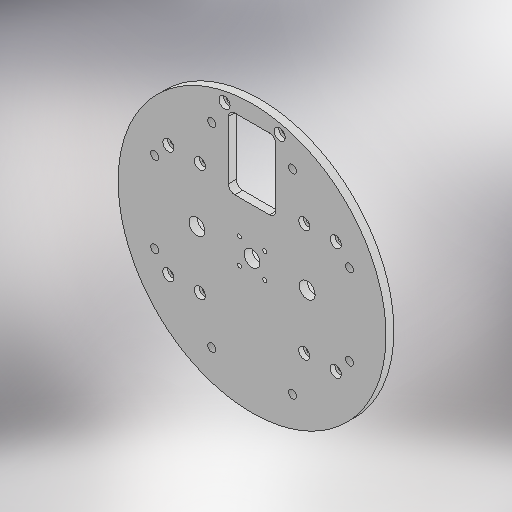
# Autodesk Inventor part: AP5.0_base-roter
Saved by Autodesk Inventor 2025.3 (Build 293356030, 356C)
## iProperties
Created: 2026-02-11
Part Number: AP5.0_base-roter
Material: 一般
Document SubType Name: Sheet Metal
Designer: ibuki_ono
Density: 1 g/cm^3
Sheet Metal Rule: Default_mm
Appearance: 既定
Author: ibuki_ono
Autodesk Inventor part; units mm, degrees
ref_plane "YZ Plane" through (0, 0, 0) normal (1, 0, 0) x (0, 1, 0)
ref_plane "XZ Plane" through (0, 0, 0) normal (0, 1, 0) x (-1, 0, 0)
ref_plane "XY Plane" through (0, 0, 0) normal (0, 0, 1) x (1, 0, 0)
sketch "スケッチ1" plane through (0, 0, 0) normal (0, 0, 1) x (1, 0, 0)
  circle A0 centre (0, 0) radius 85
  dimension "d0" = 170
  measures "d0" diameter of A0
extrude "プレート1" add sketch "スケッチ1" along normal blind 5
sketch "スケッチ2" plane through (0, 0, 5) normal (0, 0, 1) x (1, 0, 0)
  line L0 (0, 0) -> (61.8999, 25.6398) construction
  line L1 (0, 0) -> (85, 0) construction
  circle A0 centre (0, 0) radius 85 construction
  dimension "d31" = 67
  dimension "d32" = 22.5
  constraints: 4 end point, 1 horizontal, 1 horizontal alignment, 1 other
  measures "d31" distance of L0.start L0.end
  measures "d32" angle of L1 L0
hole "穴1" at (61.8999, 25.6398, 5) direction (0, 0, -1) diameter 5 end through all
thread "ねじ1" size "M6x1" class "6H" standard "ISO Metric profile" full length
pattern_circular "円形状パターン1" count 8 over 360 about axis through (0, 0, -10) along (0, 0, 1) of "穴1"
sketch "スケッチ3" plane through (0, 0, 5) normal (0, 0, 1) x (1, 0, 0)
  circle A0 centre (-25.6398, 61.8999) radius 2.5 projected
  circle A1 centre (25.6398, 61.8999) radius 2.5 projected
  line L0 (25.6398, 61.8999) -> (-25.6398, 61.8999) construction
  line L1 (0, 0) -> (0, 61.8999) construction
  line L2 (15, 29.3999) -> (15, 74.3999)
  line L3 (15, 74.3999) -> (-15, 74.3999)
  line L4 (-15, 74.3999) -> (-15, 29.3999)
  line L5 (-15, 29.3999) -> (15, 29.3999)
  line L6 (15, 29.3999) -> (-15, 74.3999) construction
  line L7 (15, 74.3999) -> (-15, 29.3999) construction
  point P0 (0, 51.8999)
  dimension "d16" = 30
  dimension "d17" = 12.5
  dimension "d18" = 45
  constraints: 16 end point, 3 midpoint, 3 parallel, 1 perpendicular, 1 point on line
  measures "d16" distance of L3.end L2.end
  measures "d17" distance between parallel lines of L0 L3
  measures "d18" distance of L3.end L4.end
extrude "押し出し1" cut sketch "スケッチ3" against normal through all contours L5 L4 L3 L2
sketch "スケッチ4" plane through (0, 0, 5) normal (0, 0, 1) x (1, 0, 0)
  circle A0 centre (-25.6398, -61.8999) radius 2.5 projected
  circle A1 centre (-25.6398, 61.8999) radius 2.5 projected
  line L0 (-25.6398, 61.8999) -> (-25.6398, -61.8999) construction
  line L1 (-25.6398, -35.6) -> (-53.1398, -35.6) construction
  point P0 (0, 0)
  point P1 (-53.1398, -35.6)
  point P2 (-33.1398, -35.6)
  dimension "d21" = 27.5
  dimension "d22" = 35.6
  dimension "d23" = 20
  constraints: 4 end point, 2 point on line, 1 coincident, 1 perpendicular
  measures "d21" distance of L1.start L1.end
  measures "d22" distance from line of point (0, 0) L1
  measures "d23" distance of point (-33.14, -35.6) L1.end
hole "穴2" at (-53.1398, -35.6, 5) at (-33.1398, -35.6, 5) direction (0, 0, -1) diameter 3.2 end through all counterbore diameter 7 counterbore depth 3
mirror "ミラー1" about plane through (0, 0, 0) normal (0, 1, 0) of "穴2"
mirror "ミラー2" about plane through (0, 0, 0) normal (1, 0, 0) of "穴2", "ミラー1"
fillet "フィレット1" radius 4 4 edges at (-15, 29.3999, 2.5) (15, 29.3999, 2.5) (15, 74.3999, 2.5) (-15, 74.3999, 2.5)
sketch "スケッチ5" plane through (0, 0, 5) normal (0, 0, 1) x (1, 0, 0)
  line L0 (-11, 74.3999) -> (11, 74.3999) projected
  line L1 (-17.5, 76.8999) -> (17.5, 76.8999) construction
  line L2 (-17.5, 76.8999) -> (17.5, 76.8999) construction
  point P0 (0, 0)
  point P1 (0, 76.8999)
  point P2 (0, 74.3999)
  dimension "d34" = 35
  dimension "d35" = 0
  dimension "d36" = 2.5
  constraints: 4 end point, 2 coincident, 2 horizontal, 2 midpoint, 1 collinear, 1 vertical alignment
  measures "d34" distance of L1.start L1.end
  measures "d35" distance between parallel lines of L1 L2
  measures "d36" distance between parallel lines of L0 L1
hole "穴3" at (-17.5, 76.8999, 5) at (17.5, 76.8999, 5) direction (0, 0, -1) diameter 3.2 end through all counterbore diameter 7 counterbore depth 3
sketch "スケッチ6" plane through (0, 0, 5) normal (0, 0, 1) x (1, 0, 0)
  line L0 (-8.025, -8.025) -> (8.025, -8.025) construction
  line L1 (8.025, -8.025) -> (8.025, 8.025) construction
  line L2 (8.025, 8.025) -> (-8.025, 8.025) construction
  line L3 (-8.025, 8.025) -> (-8.025, -8.025) construction
  line L4 (-8.025, -8.025) -> (8.025, 8.025) construction
  line L5 (8.025, -8.025) -> (-8.025, 8.025) construction
  point P0 (0, 0)
  dimension "d44" = 16.05
  dimension "d45" = 16.05
  constraints: 12 end point, 4 coincident, 2 midpoint, 2 parallel, 1 horizontal, 1 perpendicular
  measures "d44" distance of L2.end L1.end
  measures "d45" distance of L1.end L0.end
hole "穴4" at (8.025, 8.025, 5) at (8.025, -8.025, 5) at (-8.025, -8.025, 5) at (-8.025, 8.025, 5) direction (0, 0, -1) diameter 2.5 end through all
sketch "スケッチ7" plane through (0, 0, 5) normal (0, 0, 1) x (1, 0, 0)
  circle A0 centre (0, 0) radius 5
  dimension "d53" = 10
  constraints: 1 centre point, 1 coincident
  measures "d53" diameter of A0
extrude "押し出し2" cut sketch "スケッチ7" against normal through all
pattern_linear "矩形状パターン1" count 3 spacing 35 along (1, 0, 0) of "押し出し2" first direction both ways yes
equation "\"d9\" = Thickness"
equation "\"d42\" = Thickness"
equation "\"d51\" = Thickness"
equation "\"d1\" = Thickness"
equation "\"BendRadius\" = Thickness"
equation "\"BendReliefWidth\" = Thickness"
equation "\"BendReliefDepth\" = 0.5 * Thickness"
equation "\"TransitionRadius\" = BendRadius"
equation "\"JacobiRadiusSize\" = BendRadius"
equation "\"GapSize\" = Thickness"
equation "\"Thickness\" = 5"
